Autodesk Fusion 360 part; units mm, degrees
(part 3 of 3)
sketch "Sketch3" plane through (0, 0, 0) normal (0, 1, 0) x (1, 0, 0)
  line L0 (0, 0) -> (1.4945, 0) construction
  line L1 (1.4945, 0) -> (36.4945, 0) construction
  line L2 (36.4945, 0) -> (61.4945, 0) construction
  line L3 (0, -125) -> (0, 143.7262)
  line L4 (-125, 0) -> (131.9306, 0)
  line L5 (0, 0) -> (0, -40)
  line L6 (0, -40) -> (0, -70)
  line L7 (2.6, -1.9) -> (30.9156, -22.4725) construction
  line L8 (2.6, -1.9) -> (37.6, -1.9) construction
  line L9 (30.9156, -22.4725) -> (51.141, -37.1671) construction
  line L10 (2.6, -1.9) -> (44, -59)
  line L11 (2.6, -1.9) -> (71, -24)
  line L12 (3.4653, 0) -> (71, -22)
  line L13 (1, 3) -> (50, 70)
  line L14 (2.6, 1.9) -> (44, 59)
  line L15 (2.6, 1.9) -> (71, 24)
  line L16 (3.4653, 0) -> (71, 22)
  arc A0 (34.5728, -48.9057) -> (-34.5728, -48.9057) centre (0, -70) ccw
  arc A1 (38.2825, -53.9781) -> (-35.7391, -48.9057) centre (0, -70) ccw
  line L17 (-34.5728, -48.9057) -> (-35.7728, -48.9057)
  line L18 (34.5728, -48.9057) -> (35.5652, -48.6139)
  arc A2 (60.3972, -20.5742) -> (38.3698, -51.2346) centre (51.141, -37.1671) ccw
  arc A3 (63.7806, -21.6674) -> (40.4045, -54.041) centre (51.141, -37.1671) ccw
  arc A4 (35.8596, -12.6462) -> (23.2017, -30.3144) centre (30.9156, -22.4725) ccw
  arc A5 (39.0942, -13.6913) -> (22.0787, -30.591) centre (30.9156, -22.4725) ccw
  line L19 (23.0653, -30.1779) -> (21.9736, -30.475)
  line L20 (35.0137, -12.2644) -> (35.3218, -11.3107)
  line L21 (58.1388, -19.5027) -> (58.5398, -18.2616)
  line L22 (37.1836, -50.0586) -> (36.3714, -50.6526)
  arc A6 (56.8491, 17.3902) -> (56.8491, -17.3902) centre (61.4945, 0) ccw
  arc A7 (61.784, 18.9978) -> (61.784, -18.9978) centre (61.4945, 0) ccw
  arc A8 (35.5735, 10.4595) -> (35.5735, -10.4595) centre (36.4945, 0) ccw
  arc A9 (38.32, 11.3542) -> (38.32, -11.3542) centre (36.4945, 0) ccw
  line L23 (56.5665, -17.2982) -> (56.2524, -18.2625)
  line L24 (61.2051, 18.9978) -> (60.8806, 18.0017)
  line L25 (34.7818, 10.3594) -> (34.7818, 11.3717)
  line L26 (34.1123, -10.2262) -> (33.8953, -11.2024)
  line L27 (54.8109, 17.7856) -> (55.0055, 16.7897)
  arc A10 (61.784, 18.9978) -> (61.784, -18.9978) centre (61.4945, 0) ccw
  arc A11 (56.8491, 17.3902) -> (56.8491, -17.3902) centre (61.4945, 0) ccw
  line L28 (54.8109, -17.7856) -> (55.0055, -16.7897)
  line L29 (56.5665, 17.2982) -> (56.2524, 18.2625)
  arc A12 (38.32, 11.3542) -> (38.32, -11.3542) centre (36.4945, 0) ccw
  arc A13 (35.5735, 10.4595) -> (35.5735, -10.4595) centre (36.4945, 0) ccw
  line L30 (34.7818, -10.3594) -> (34.7818, -11.3717)
  line L31 (34.1123, 10.2262) -> (33.8953, 11.2024)
  arc A14 (23.2017, 30.3144) -> (35.8596, 12.6462) centre (30.9156, 22.4725) ccw
  arc A15 (25.1441, 32.9934) -> (39.0942, 13.6913) centre (30.9156, 22.4725) ccw
  line L32 (35.0137, 12.2644) -> (35.3218, 11.3107)
  arc A16 (40.4045, 54.041) -> (63.7806, 21.6674) centre (51.141, 37.1671) ccw
  arc A17 (38.3698, 51.2346) -> (60.3972, 20.5742) centre (51.141, 37.1671) ccw
  line L33 (23.0653, 30.1779) -> (21.9736, 30.475)
  line L34 (58.1388, 19.5027) -> (58.5398, 18.2616)
  line L35 (34.5728, 48.9057) -> (35.5652, 48.6139)
  line L36 (37.1836, 50.0586) -> (36.3714, 50.6526)
  arc A18 (-34.5728, 48.9057) -> (34.5728, 48.9057) centre (0, 70) ccw
  arc A19 (-38.2825, 53.9781) -> (38.2825, 53.9781) centre (0, 70) ccw
  line L37 (-34.5728, 48.9057) -> (-35.7728, 48.9057)
  line L38 (-19.1834, 27.3115) -> (-20.2351, 27.0949)
  line L39 (-21.296, -28.9329) -> (-20.4294, -29.5667)
  line L40 (18.3127, -26.0844) -> (19.4114, -25.8863)
  arc A20 (18.3127, -26.0844) -> (-20.6447, -29.8611) centre (0, -40) ccw
  arc A21 (22.0787, -30.591) -> (22.0231, -30.4615) centre (0, -40) ccw
  arc A22 (19.4114, -25.8863) -> (-21.296, -28.9329) centre (0, -40) ccw
  line L41 (26.8699, -38.3732) -> (50, -70)
  line L42 (-30.5795, -43.4455) -> (-34.5728, -48.9057)
  arc A23 (-19.1834, 27.3115) -> (20.6447, 29.8611) centre (0, 40) ccw
  arc A24 (-20.2351, 27.0949) -> (22.968, 33.0379) centre (0, 40) ccw
  line L43 (17.4272, 24.9903) -> (18.2369, 24.3982)
  line L44 (34.0604, 47.5715) -> (35.2429, 47.5715)
  arc A25 (-35.8596, 12.6462) -> (-23.2017, 30.3144) centre (-30.9156, 22.4725) ccw
  arc A26 (-39.0942, 13.6913) -> (-25.1441, 32.9934) centre (-30.9156, 22.4725) ccw
  line L45 (-35.0137, 12.2644) -> (-35.3218, 11.3107)
  arc A27 (-35.5735, -10.4595) -> (-35.5735, 10.4595) centre (-36.4945, 0) ccw
  arc A28 (-38.32, -11.3542) -> (-38.32, 11.3542) centre (-36.4945, 0) ccw
  line L46 (-23.0653, 30.1779) -> (-21.9736, 30.475)
  arc A29 (-63.7806, 21.6674) -> (-40.4045, 54.041) centre (-51.141, 37.1671) ccw
  arc A30 (-60.3972, 20.5742) -> (-38.3698, 51.2346) centre (-51.141, 37.1671) ccw
  line L47 (-37.1836, 50.0586) -> (-36.3714, 50.6526)
  line L48 (-58.1388, 19.5027) -> (-58.5398, 18.2616)
  arc A31 (-56.8491, -17.3902) -> (-56.8491, 17.3902) centre (-61.4945, 0) ccw
  line L49 (-3.4653, 0) -> (-71, 22)
  line L50 (-54.8109, 17.7856) -> (-55.0055, 16.7897)
  line L51 (-34.7818, 10.3594) -> (-34.7818, 11.3717)
  arc A32 (-61.784, -18.9978) -> (-61.784, 18.9978) centre (-61.4945, 0) ccw
  line L52 (-34.1123, -10.2262) -> (-33.8953, -11.2024)
  line L53 (-35.0137, -12.2644) -> (-35.3218, -11.3107)
  arc A33 (-22.0787, -30.591) -> (-39.0942, -13.6913) centre (-30.9156, -22.4725) ccw
  arc A34 (-23.2017, -30.3144) -> (-35.8596, -12.6462) centre (-30.9156, -22.4725) ccw
  line L54 (-54.8109, -17.7856) -> (-55.0055, -16.7897)
  arc A35 (-40.4045, -54.041) -> (-63.7806, -21.6674) centre (-51.141, -37.1671) ccw
  arc A36 (-38.3698, -51.2346) -> (-60.3972, -20.5742) centre (-51.141, -37.1671) ccw
  line L55 (-58.1388, -19.5027) -> (-58.5398, -18.2616)
  line L56 (-23.0653, -30.1779) -> (-21.9736, -30.475)
  line L57 (-37.1836, -50.0586) -> (-36.3714, -50.6526)
  point P0 (-44, -59)
  dimension "d201" = 35
  dimension "d202" = 25
  dimension "d205" = 36
  dimension "d206" = 38
  dimension "d207" = 21
  dimension "d209" = 40
  dimension "d210" = 30
  dimension "d213" = 81
  dimension "d214" = 83
  dimension "d215" = 35
  dimension "d216" = 36
  dimension "d217" = 25
  dimension "d218" = 22
  dimension "d220" = 38
  dimension "d221" = 40
  dimension "d222" = 1.2
  constraint coincident L0.start L5.start
  constraint horizontal L0
  constraint parallel L0 L1
  constraint parallel L1 L2
  constraint coincident L2.end A6.centre
  constraint concentric A6 A7
  constraint coincident L1.end L2.start
  constraint perpendicular L0 L3
  constraint horizontal L4
  constraint perpendicular L4 L5
  constraint perpendicular L4 L6
  constraint coincident L6.end A0.centre
  constraint concentric A0 A1
  constraint horizontal L8
  constraint parallel L7 L9
  constraint coincident L7.end L9.start
  constraint coincident L9.end A2.centre
  constraint concentric A2 A3
  constraint midpoint L4 L12.start
  constraint symmetric L4 L7.start L14.start
  constraint symmetric L4 L41.end L13.end
  constraint symmetric L4 L10.end L14.end
  constraint symmetric L4 L11.end L15.end
  constraint symmetric L4 L12.start L16.start
  constraint symmetric L4 L12.end L16.end
  constraint symmetric L3 L10.end P0
  constraint horizontal L17
  constraint coincident A1 L18.end
  constraint coincident L10 A2.end
  constraint coincident L11 A2.start
  constraint coincident L10 A3.end
  constraint coincident L11 A3.start
  constraint coincident L11 A4.start
  constraint coincident L10 A4.end
  constraint coincident L11 A5.start
  constraint coincident A4 L19.start
  constraint coincident A5 L19.end
  constraint coincident A4 L20.start
  constraint coincident A5 L20.end
  constraint perpendicular L11 L20
  constraint coincident A2 L21.start
  constraint parallel L20 L21
  constraint coincident A2 L22.start
  constraint coincident A3 L22.end
  constraint coincident L16 A6.start
  constraint coincident L12 A6.end
  constraint coincident L12 A7.end
  constraint coincident L16 A7.start
  constraint coincident L16 A8.start
  constraint coincident L12 A8.end
  constraint coincident L12 A9.end
  constraint coincident L16 A9.start
  constraint coincident L12 L23.start
  constraint coincident A7 L23.end
  constraint perpendicular L12 L23
  constraint coincident A7 L24.start
  constraint parallel L23 L24
  constraint coincident A8 L25.start
  constraint coincident A9 L25.end
  constraint vertical L25
  constraint coincident A8 L26.start
  constraint coincident A9 L26.end
  constraint coincident A7 L27.start
  constraint coincident A6 L27.end
  constraint coincident L16 L27.end
  constraint symmetric L4 A0.end A18.start
  constraint symmetric L4 A0 A18
  constraint symmetric L4 A1 A19
  constraint symmetric L4 A0.start L35.start
  constraint symmetric L4 A1.start A19.end
  constraint symmetric L4 L17.end L37.end
  constraint symmetric L4 L18.end L35.end
  constraint symmetric L4 A2.end A17.start
  constraint symmetric L4 A2.start A17.end
  constraint symmetric L4 A2 A17
  constraint symmetric L4 A3.end A16.start
  constraint symmetric L4 A3.start A16.end
  constraint symmetric L4 A3 A16
  constraint symmetric L4 A4.start A14.end
  constraint symmetric L4 A4.end A14.start
  constraint symmetric L4 A4 A14
  constraint symmetric L4 A5.start A15.end
  constraint symmetric L4 A5 A15
  constraint symmetric L4 L19.start L33.start
  constraint symmetric L4 L19.end L33.end
  constraint symmetric L4 L20.start L32.start
  constraint symmetric L4 L20.end L32.end
  constraint symmetric L4 L21.start L34.start
  constraint symmetric L4 L21.end L34.end
  constraint symmetric L4 L22.start L36.start
  constraint symmetric L4 L22.end L36.end
  constraint symmetric L4 A6.start A6.end
  constraint symmetric L4 A6 A11
  constraint symmetric L4 A6.end A6.start
  constraint symmetric L4 A7.end A7.start
  constraint symmetric L4 A7 A10
  constraint symmetric L4 A7.start A7.end
  constraint symmetric L4 A8.start A8.end
  constraint symmetric L4 A8.end A8.start
  constraint symmetric L4 A8 A13
  constraint symmetric L4 A9.end A9.start
  constraint symmetric L4 A9.start A9.end
  constraint symmetric L4 A9 A12
  constraint symmetric L4 L23.start L29.start
  constraint symmetric L4 L23.end L29.end
  constraint symmetric L4 L25.start L30.start
  constraint symmetric L4 L25.end L30.end
  constraint symmetric L4 L26.start L31.start
  constraint symmetric L4 L26.end L31.end
  constraint symmetric L4 L27.start L28.start
  constraint symmetric L4 L27.end L28.end
  constraint coincident A5 L40.end
  constraint coincident L17 A1.end
  constraint coincident L19 A21.end
  constraint concentric A21 A22
  constraint coincident A1 L41.start
  constraint coincident A0 L42.start
  constraint coincident L13 A23.end
  constraint coincident L13 A24.end
  constraint coincident A23 L43.start
  constraint coincident A24 L43.end
  constraint perpendicular L13 L43
  constraint coincident A16 L44.start
  constraint coincident A17 L44.end
  constraint horizontal L44
  constraint symmetric L3 L12.start L49.start
  constraint symmetric L3 L16.end L49.end
  constraint symmetric L3 A2.end A36.start
  constraint symmetric L3 A2.start A36.end
  constraint symmetric L3 A2 A36
  constraint symmetric L3 A3.end A35.start
  constraint symmetric L3 A3.start A35.end
  constraint symmetric L3 A3 A35
  constraint symmetric L3 A4.start A34.end
  constraint symmetric L3 A4.end A34.start
  constraint symmetric L3 A4 A34
  constraint symmetric L3 A5.start A33.end
  constraint symmetric L3 A5 A33
  constraint symmetric L3 L19.start L56.start
  constraint symmetric L3 L19.end L56.end
  constraint symmetric L3 L20.start L53.start
  constraint symmetric L3 L20.end L53.end
  constraint symmetric L3 L21.start L55.start
  constraint symmetric L3 L21.end L55.end
  constraint symmetric L3 L22.start L57.start
  constraint symmetric L3 L22.end L57.end
  constraint symmetric L3 A7.end A32.start
  constraint symmetric L3 A7 A32
  constraint symmetric L3 A7.start A32.end
  constraint symmetric L3 A8.start A27.end
  constraint symmetric L3 A8.end A27.start
  constraint symmetric L3 A8 A27
  constraint symmetric L3 L25.start L51.start
  constraint symmetric L3 L25.end L51.end
  constraint symmetric L3 L26.start L52.start
  constraint symmetric L3 L26.end L52.end
  constraint symmetric L3 L27.start L50.start
  constraint symmetric L3 L27.end L50.end
  constraint symmetric L3 A6.end A31.start
  constraint symmetric L3 A6.start A31.end
  constraint symmetric L3 A11 A31
  constraint symmetric L3 L28.start L54.start
  constraint symmetric L3 L28.end L54.end
  constraint symmetric L3 A9.end A28.start
  constraint symmetric L3 A9.start A28.end
  constraint symmetric L3 A12 A28
  constraint symmetric L3 A14.end A25.start
  constraint symmetric L3 A14.start A25.end
  constraint symmetric L3 A14 A25
  constraint symmetric L3 A15.end A26.start
  constraint symmetric L3 A15.start A26.end
  constraint symmetric L3 A15 A26
  constraint symmetric L3 L32.start L45.start
  constraint symmetric L3 L32.end L45.end
  constraint symmetric L3 A16.end A29.start
  constraint symmetric L3 A16.start A29.end
  constraint symmetric L3 A16 A29
  constraint symmetric L3 A17.end A30.start
  constraint symmetric L3 A17.start A30.end
  constraint symmetric L3 A17 A30
  constraint symmetric L3 L33.start L46.start
  constraint symmetric L3 L33.end L46.end
  constraint symmetric L3 L34.start L48.start
  constraint symmetric L3 L34.end L48.end
  constraint symmetric L3 L36.start L47.start
  constraint symmetric L3 L36.end L47.end
  constraint symmetric L3 A5.end A33.start
  measures "d201" distance of L0.end L1.end
  measures "d202" distance of L1.end L2.end
  measures "d205" diameter of A6
  measures "d206" diameter of A7
  measures "d207" diameter of A8
  measures "d209" distance of L0.start L5.end
  measures "d210" distance of L5.end L6.end
  measures "d213" diameter of A0
  measures "d214" diameter of A1
  measures "d215" distance of L7.start L7.end
  measures "d216" angle of L7 L8
  measures "d217" distance of L7.end L9.end
  measures "d218" diameter of A4
  measures "d220" diameter of A2
  measures "d221" diameter of A3
  measures "d222" distance of A0.end L17.end
extrude "Extrude4" add sketch "Sketch3" along normal blind 2 contours L3 L5 A0 A1 L17 A35 | L3 L5 A0 A1 L41 | L3 L5 L39 A20 A22 A33 | L3 L5 L40 A20 A22 | A1 L17 A32 A35 A36 L55 L57 | L4 A31 A32 L54 A35 | L39 A22 A28 L53 A33 A34 L56 | L10 L11 A2 A3 | L4 A31 L49 A32 | L3 L38 A23 A24 A26 | L3 L13 A23 A24 | L10 L11 A4 A5 | L4 A27 A28 L52 A33 | L4 A27 A28 L49 | L38 A24 A25 A26 L45 A28 L46 | L4 L16 A8 A9 A12 A13 | L4 L12 A8 A9 A12 A13 | A19 A29 A30 L47 L48 A32 | L3 A18 A19 L37 A29 | L3 L13 A18 A19 | L4 L12 A6 A7 A10 A11 | L4 L16 A6 A7 A10 A11 | L14 L15 A14 A15 | L14 L15 A16 A17
equation "d141 = ( 19.324 / 2 ) * 1 mm"
equation "d142 = ( 19.324 / 2 ) * 1 mm"
